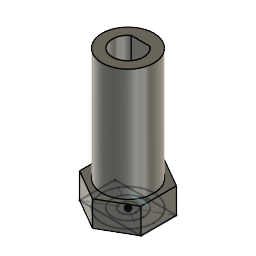
Wheel axel connector (Autodesk Fusion 360 design; units mm, degrees)
Autodesk Fusion 360 part; units mm, degrees
note: some values were not read from the file. Set by a fixed rule: which face or edge a step refers to.
sketch "Sketch1" plane through (0, 0, 0) normal (0, 0, 1) x (1, 0, 0)
  line L0 (6, -3.462) -> (-6, -3.462)
  line L1 (-6, -3.462) -> (-6, 3.462)
  line L2 (-6, 3.462) -> (6, 3.462)
  line L3 (6, 3.462) -> (6, -3.462)
  line L4 (6, -3.462) -> (-6, 3.462) construction
  line L5 (-6, -3.462) -> (6, 3.462) construction
  circle A0 centre (0, 0) radius 3.05
  circle A1 centre (0, 0) radius 5.05
  circle A2 centre (0, 0) radius 1.55
  line L6 (1.8166, 2.45) -> (-1.8166, 2.45)
  dimension "d1" = 12
  dimension "d2" = 6.924
  dimension "d8" = 6.1
  dimension "d9" = 10.1
  dimension "d16" = 3.1
  constraint horizontal L0
  constraint perpendicular L0 L1
  constraint parallel L0 L2
  constraint parallel L1 L3
  constraint coincident L4 A0.centre
  constraint coincident L5 A0.centre
  constraint coincident A0.centre A1.centre
  constraint coincident A0 L6.start
  constraint coincident A0 L6.end
  measures "d1" distance of L1.end L2.end
  measures "d2" distance of L0.end L1.end
  measures "d8" diameter of A0
  measures "d9" diameter of A1
  measures "d16" diameter of A2
extrude "Extrude1" add sketch "Sketch1" along normal blind 5 contours L0 L2 L3 A1 | L0 L2 A1 | L0 L1 L2 A1 | A0 L6 | A0 L6 | A2 makes body 1
pattern_circular "C-Pattern1" count 3 over 360 about axis through (0, 0, 1.75) along (0, 0, 1) of bodies 1 makes body 2 at (2.3854, 2.7923, 1.6667) makes body 3 at (-3.6109, 0.6697, 1.6667)
combine "Combine1" operation add target body 3 tool bodies 2 1
move_face "OffsetFaces1" offset 0.0021 20 faces at (-0.0006, -6.9251, 1.6667) (0.0006, -6.9251, 3.3333) (-0.0006, -6.9251, 1.6667) (0.0006, -6.9251, 3.3333) (-5.9976, -3.4641, 1.6667) (-5.9976, -3.462, 1.6667) (-5.9988, 3.462, 3.3333) (-5.997, 3.4631, 1.6667) (-5.9988, 3.462, 3.3333) (-5.997, 3.4631, 1.6667) (-0.0006, 6.9251, 3.3333) (0.0006, 6.9251, 1.6667) (-0.0006, 6.9251, 3.3333) (0.0006, 6.9251, 1.6667) (5.9976, 3.4641, 1.6667) (5.9976, 3.462, 1.6667) (5.997, -3.4631, 1.6667) (5.9988, -3.462, 3.3333) (5.997, -3.4631, 1.6667) (5.9988, -3.462, 3.3333) on bodies 3
extrude "Extrude2" cut sketch "Sketch1" along normal blind 27 contours A0 L6 | A0 L6 | A2 bodies 3
extrude "Extrude3" add sketch "Sketch1" along normal blind 27 contours L0 A1 | L0 L2 A1 | L2 A1 | A0 L6 picked at (0.1935, 2.7248) bodies 3
extrude "Extrude4" add sketch "Sketch1" along normal blind 5 contours A0 L6 | A0 L6 bodies 3
